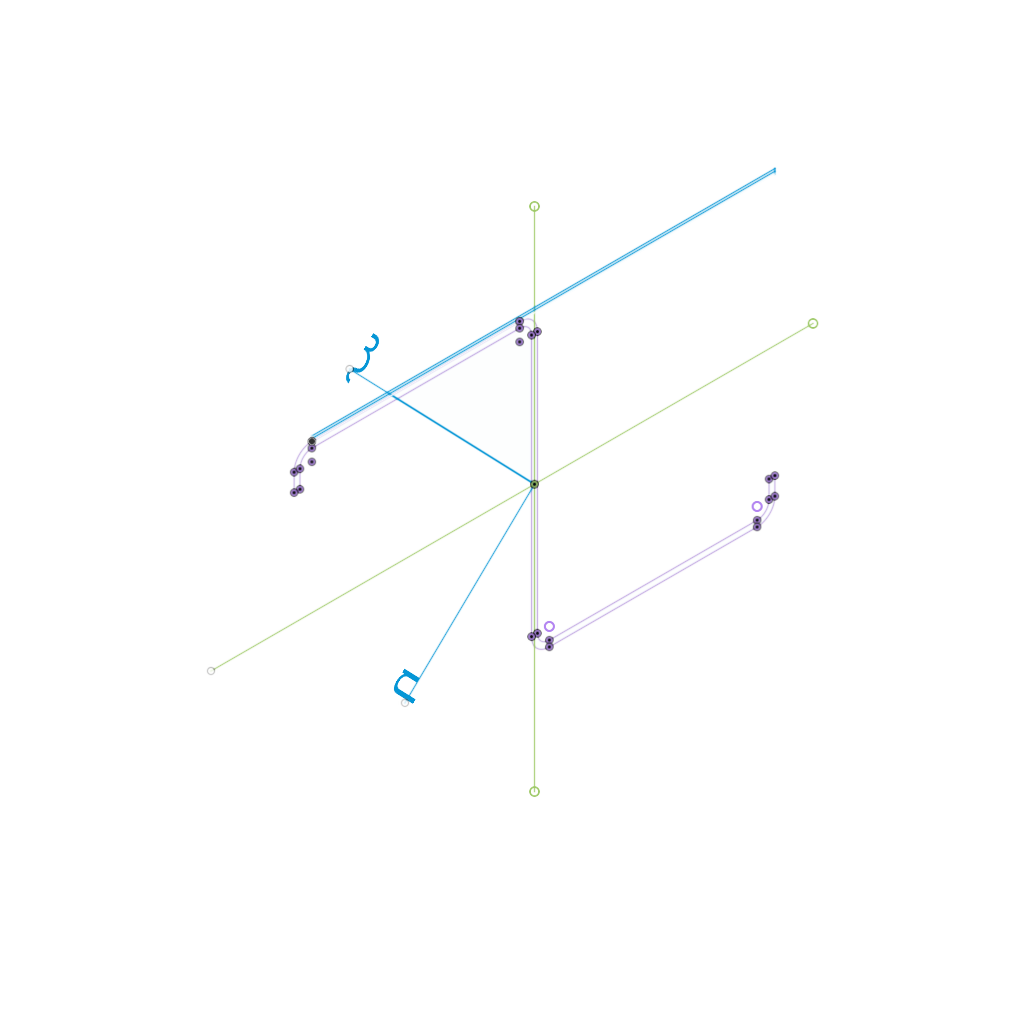
Modelo_3D (Autodesk Fusion 360 archive; units mm, degrees)
design "Configuration 1"
part number: 2026-10-21-11-30-17-065
Autodesk Fusion 360 part; units mm, degrees
sketch "Sketch1" plane through (0, 0, 0) normal (1, 0, 0) x (0, 0, -1)
  line L0 (49.5, 3, -90.5) -> (49.5, 47, -90.5)
  line L1 (50.5, 47, -90.5) -> (50.5, 3, -90.5)
  line L2 (52.5, 50, -90.5) -> (87.5, 50, -90.5)
  line L3 (87.5, 49, -90.5) -> (52.5, 49, -90.5)
  line L4 (12.5, 1, -90.5) -> (47.5, 1, -90.5)
  line L5 (9.5, 3, -90.5) -> (9.5, 6, -90.5)
  line L6 (9.5, 6, -90.5) -> (10.5, 6, -90.5)
  line L7 (10.5, 6, -90.5) -> (10.5, 3, -90.5)
  arc A0 through (10.5, 3, -90.5) (11.0858, 1.5858, -90.5) (12.5, 1, -90.5)
  arc A1 through (52.5, 49, -90.5) (51.0858, 48.4142, -90.5) (50.5, 47, -90.5)
  line L8 (12.5, 0, -90.5) -> (47.5, 0, -90.5)
  arc A2 through (47.5, 1, -90.5) (48.9142, 1.5858, -90.5) (49.5, 3, -90.5)
  line L9 (90.5, 47, -90.5) -> (90.5, 44, -90.5)
  line L10 (90.5, 44, -90.5) -> (89.5, 44, -90.5)
  line L11 (89.5, 44, -90.5) -> (89.5, 47, -90.5)
  arc A3 through (89.5, 47, -90.5) (88.9142, 48.4142, -90.5) (87.5, 49, -90.5)
  arc A4 through (52.5, 50, -90.5) (50.3787, 49.1213, -90.5) (49.5, 47, -90.5)
  arc A5 through (90.5, 47, -90.5) (89.6213, 49.1213, -90.5) (87.5, 50, -90.5)
  arc A6 through (9.5, 3, -90.5) (10.3787, 0.8787, -90.5) (12.5, 0, -90.5)
  arc A7 through (47.5, 0, -90.5) (49.6213, 0.8787, -90.5) (50.5, 3, -90.5)
  dimension "d21" = 3
  dimension "d22" = 3
  dimension "d24" = 3
extrude "Extrude1" add sketch "Sketch1" along normal blind 50 contours L0 L1 L2 L3 L4 L5 L6 L7 A0 A1 L8 A2 L9 L10 L11 A3 A4 A5 A6 A7 in plane through (-90.5, 0, 0) normal (1, 0, 0) makes body 1
ref_plane "WorkPlane2" through (-90.5, 25, -50) normal (1, 0, 0) x (0, 0, -1)
move_body "Move4" bodies 1 to x (1, 0, 0) y (0, 1, 0) z (0, 0, 1) at (90.5, 0, 9.5)
ref_plane "WorkPlane3" through (0, 25, -40.5) normal (-1, 0, 0) x (0, 0, 1)
sketch "Sketch6" plane through (0, 0, 0) normal (-1, 0, 0) x (0, 0, 1)
  arc A0 (-3, 0) -> (0, 3) centre (-3, 3) ccw
  line L0 (0, 3) -> (0, 6)
  line L1 (0, 6) -> (-1, 6)
  line L2 (-1, 6) -> (-1, 3)
  arc A1 (-3, 1) -> (-1, 3) centre (-3, 3) ccw
  line L3 (-3, 1) -> (-38, 1)
  arc A2 (-40, 3) -> (-38, 1) centre (-38, 3) ccw
  line L4 (-40, 3) -> (-40, 47)
  arc A3 (-40, 47) -> (-43, 50) centre (-43, 47) ccw
  line L5 (-43, 50) -> (-78, 50)
  arc A4 (-78, 50) -> (-81, 47) centre (-78, 47) ccw
  line L6 (-81, 47) -> (-81, 44)
  line L7 (-81, 44) -> (-80, 44)
  line L8 (-80, 44) -> (-80, 47)
  arc A5 (-78, 49) -> (-80, 47) centre (-78, 47) ccw
  line L9 (-78, 49) -> (-43, 49)
  arc A6 (-41, 47) -> (-43, 49) centre (-43, 47) ccw
  line L10 (-41, 47) -> (-41, 3)
  arc A7 (-41, 3) -> (-38, 0) centre (-38, 3) ccw
  line L11 (-38, 0) -> (-3, 0)
  line L12 (-81, 44) -> (-80, 44)
  line L13 (-80, 47) -> (-80, 44)
  line L14 (-81, 44) -> (-81, 47)
  line L15 (-78, 50) -> (-43, 50)
  line L16 (-43, 49) -> (-78, 49)
  line L17 (-41, 47) -> (-41, 3)
  line L18 (-38, 0) -> (-3, 0)
  line L19 (-38, 1) -> (-3, 1)
  line L20 (-1, 3) -> (-1, 6)
  line L21 (-1, 6) -> (0, 6)
  line L22 (0, 6) -> (0, 3)
  arc A8 (-3, 0) -> (0, 3) centre (-3, 3) ccw
  arc A9 (-3, 1) -> (-1, 3) centre (-3, 3) ccw
  arc A10 (-40, 5.2361) -> (-40.0006, 5.2355) centre (-38, 3) ccw
  arc A11 (-41, 3) -> (-38, 0) centre (-38, 3) ccw
  arc A12 (-40, 3) -> (-38, 1) centre (-38, 3) ccw
  arc A13 (-41, 47) -> (-43, 49) centre (-43, 47) ccw
  arc A14 (-78, 49) -> (-80, 47) centre (-78, 47) ccw
  arc A15 (-78, 50) -> (-81, 46.9985) centre (-78, 47) ccw
  line L23 (-40, 47) -> (-40, 3)
  arc A16 (-40, 47) -> (-43, 50) centre (-43, 47) ccw
  constraint coincident L6.end L7.start
  constraint coincident L7.end L8.start
  constraint coincident L8.end A5.end
  constraint coincident A4.end L6.start
  constraint coincident L5.end A4.start
  constraint coincident A3.end L5.start
  constraint coincident L9.end A6.end
  constraint coincident A5.start L9.start
  constraint coincident A6.start L10.start
  constraint coincident L10.end A7.start
  constraint coincident A7.end L11.start
  constraint coincident A0.start L11.end
  constraint coincident L3.end A2.end
  constraint coincident A1.start L3.start
  constraint coincident L2.end A1.end
  constraint coincident L1.end L2.start
  constraint coincident L0.end L1.start
  constraint coincident A0.end L0.start
  constraint concentric A0 A9
  constraint coincident L2.end A9
  constraint concentric A0 A8
  constraint concentric A2 A12
  constraint concentric A2 A11
  constraint coincident A7.end A11
  constraint coincident L4 A10.start
  constraint concentric A10 A11
  constraint concentric A6 A13
  constraint coincident L9.end A13
  constraint concentric A5 A15
  constraint coincident A4.end A15
  constraint concentric A4 A14
  constraint coincident A5.start A14
  constraint coincident L6 A15.end
  constraint coincident L4.end A3.start
  constraint coincident A2.start L4.start
  constraint concentric A3 A16
move_body "Move5" bodies 1 to x (1, 0, 0) y (0, 1, 0) z (0, 0, 1) at (0, 0, 80)
move_body "Move6" bodies 1 to x (1, 0, 0) y (0, 1, 0) z (0, 0, 1) at (0, -50, 0)
ref_plane "WorkPlane4" through (25, 0, 19.5) normal (0, 1, 0) x (0, 0, 1)
mirror "Mirror1" about plane through (25, 0, 19.5) normal (0, 1, 0) of bodies 1 makes body 2
move_body "Move7" bodies 2 to x (1, 0, 0) y (0, 1, 0) z (0, 0, 1) at (0, 0, 1)
sketch "Sketch8" plane through (0, 0, 0) normal (-1, 0, 0) x (0, 0, 1)
  arc A0 (81, 47) -> (78, 50) centre (78, 47) ccw
  line L0 (78, 50) -> (43, 50)
  arc A1 (43, 50) -> (40, 47) centre (43, 47) ccw
  line L1 (40, 47) -> (40, 3)
  arc A2 (38, 1) -> (40, 3) centre (38, 3) ccw
  line L2 (38, 1) -> (3, 1)
  arc A3 (1, 3) -> (3, 1) centre (3, 3) ccw
  line L3 (1, 3) -> (1, 6)
  line L4 (1, 6) -> (0, 6)
  line L5 (0, 6) -> (0, 3)
  arc A4 (0, 3) -> (3, 0) centre (3, 3) ccw
  line L6 (3, 0) -> (38, 0)
  arc A5 (38, 0) -> (41, 3) centre (38, 3) ccw
  line L7 (41, 3) -> (41, 47)
  arc A6 (43, 49) -> (41, 47) centre (43, 47) ccw
  line L8 (43, 49) -> (78, 49)
  arc A7 (80, 47) -> (78, 49) centre (78, 47) ccw
  line L9 (80, 47) -> (80, 44)
  line L10 (80, 44) -> (81, 44)
  line L11 (81, 44) -> (81, 47)
  line L12 (78, 50) -> (0, 50)
  line L13 (0, 50) -> (0, 50.8)
  line L14 (0, 50.8) -> (78, 50.8)
  line L15 (78, 50.8) -> (78, 50)
  line L16 (78, 50.4) -> (0, 50.4)
  line L17 (40.5, 24.9903) -> (71.6375, 57.3625)
  line L18 (40.5, 24.9903) -> (62.3226, 4)
  line L19 (40.5, 24.9903) -> (64.9406, 50.4)
  line L20 (40.5, 24.9903) -> (40.5, 65.5254)
  line L21 (40.5, 24.9903) -> (40.5, -19.8542)
  line L22 (40.5, 24.9903) -> (95, 24.9903)
  line L23 (40.5, 24.9903) -> (-6.4154, 24.9903)
  dimension "d45" = 35.2561
  dimension "d46" = 43.886
  dimension "d47" = 5
  dimension "d49" = 5
  constraint horizontal L12
  constraint vertical L13
  constraint horizontal L14
  constraint vertical L15
  constraint coincident A0.end L0.start
  constraint midpoint L15 L16.start
  constraint midpoint L13 L16.end
  constraint coincident L17.start L18.start
  constraint perpendicular L17 L18
  constraint perpendicular L18 L19
  constraint coincident L16 L19.end
  constraint parallel L1 L20
  constraint parallel L20 L21
  constraint perpendicular L21 L22
  constraint perpendicular L20 L23
  measures "d45" distance of L17.start L19.end
  measures "d46" angle of L17 L20
delete_body "RemoveBody1" bodies 1
hidden bodies 2
equation "d48 = 'ξ'"
equation "d50 = 'η'"

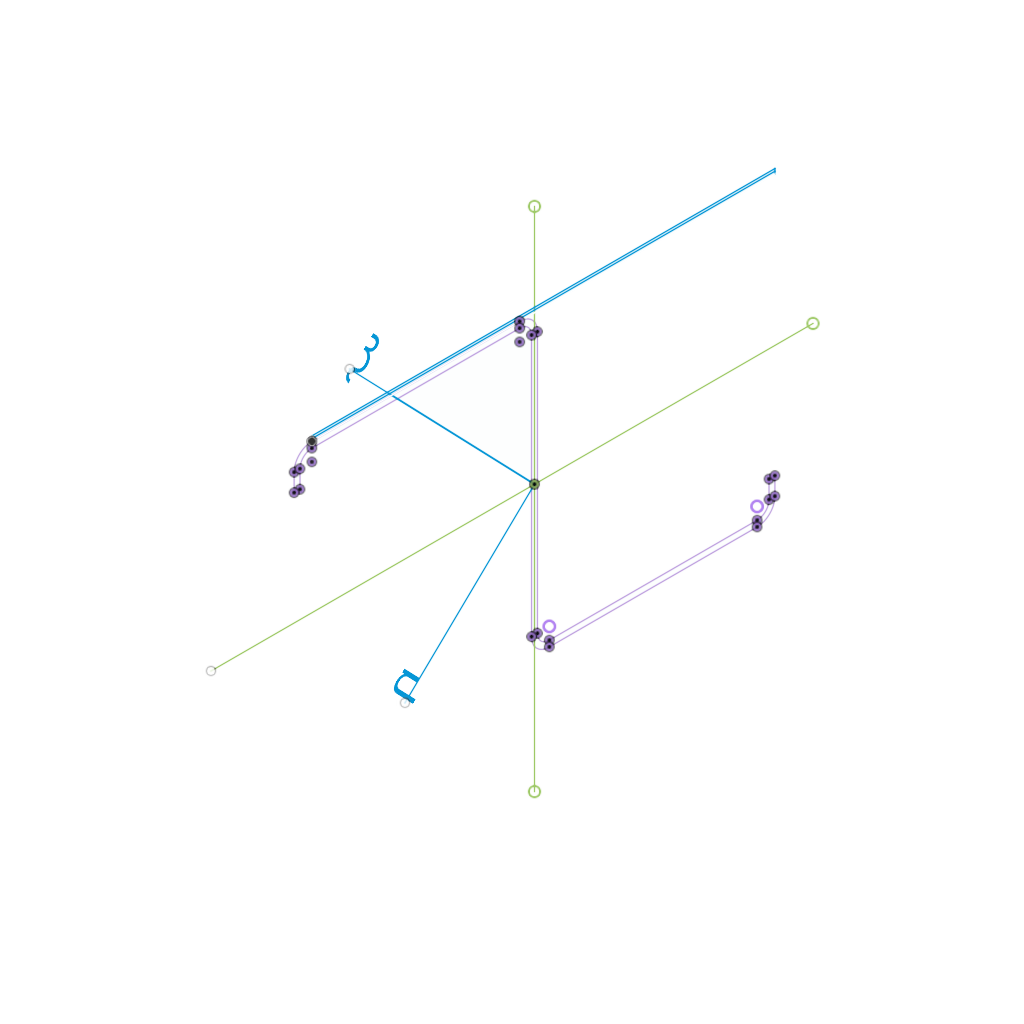
design "sketch viga z"
part number: 2026-10-21-11-30-17-065
Autodesk Fusion 360 part; units mm, degrees
sketch "Sketch1" plane through (0, 0, 0) normal (1, 0, 0) x (0, 0, -1)
  line L0 (49.5, 3, -90.5) -> (49.5, 47, -90.5)
  line L1 (50.5, 47, -90.5) -> (50.5, 3, -90.5)
  line L2 (52.5, 50, -90.5) -> (87.5, 50, -90.5)
  line L3 (87.5, 49, -90.5) -> (52.5, 49, -90.5)
  line L4 (12.5, 1, -90.5) -> (47.5, 1, -90.5)
  line L5 (9.5, 3, -90.5) -> (9.5, 6, -90.5)
  line L6 (9.5, 6, -90.5) -> (10.5, 6, -90.5)
  line L7 (10.5, 6, -90.5) -> (10.5, 3, -90.5)
  arc A0 through (10.5, 3, -90.5) (11.0858, 1.5858, -90.5) (12.5, 1, -90.5)
  arc A1 through (52.5, 49, -90.5) (51.0858, 48.4142, -90.5) (50.5, 47, -90.5)
  line L8 (12.5, 0, -90.5) -> (47.5, 0, -90.5)
  arc A2 through (47.5, 1, -90.5) (48.9142, 1.5858, -90.5) (49.5, 3, -90.5)
  line L9 (90.5, 47, -90.5) -> (90.5, 44, -90.5)
  line L10 (90.5, 44, -90.5) -> (89.5, 44, -90.5)
  line L11 (89.5, 44, -90.5) -> (89.5, 47, -90.5)
  arc A3 through (89.5, 47, -90.5) (88.9142, 48.4142, -90.5) (87.5, 49, -90.5)
  arc A4 through (52.5, 50, -90.5) (50.3787, 49.1213, -90.5) (49.5, 47, -90.5)
  arc A5 through (90.5, 47, -90.5) (89.6213, 49.1213, -90.5) (87.5, 50, -90.5)
  arc A6 through (9.5, 3, -90.5) (10.3787, 0.8787, -90.5) (12.5, 0, -90.5)
  arc A7 through (47.5, 0, -90.5) (49.6213, 0.8787, -90.5) (50.5, 3, -90.5)
  dimension "d21" = 3
  dimension "d22" = 3
  dimension "d24" = 3
extrude "Extrude1" add sketch "Sketch1" along normal blind 50 contours L0 L1 L2 L3 L4 L5 L6 L7 A0 A1 L8 A2 L9 L10 L11 A3 A4 A5 A6 A7 in plane through (-90.5, 0, 0) normal (1, 0, 0) makes body 1
ref_plane "WorkPlane2" through (-90.5, 25, -50) normal (1, 0, 0) x (0, 0, -1)
move_body "Move4" bodies 1 to x (1, 0, 0) y (0, 1, 0) z (0, 0, 1) at (90.5, 0, 9.5)
ref_plane "WorkPlane3" through (0, 25, -40.5) normal (-1, 0, 0) x (0, 0, 1)
sketch "Sketch6" plane through (0, 0, 0) normal (-1, 0, 0) x (0, 0, 1)
  arc A0 (-3, 0) -> (0, 3) centre (-3, 3) ccw
  line L0 (0, 3) -> (0, 6)
  line L1 (0, 6) -> (-1, 6)
  line L2 (-1, 6) -> (-1, 3)
  arc A1 (-3, 1) -> (-1, 3) centre (-3, 3) ccw
  line L3 (-3, 1) -> (-38, 1)
  arc A2 (-40, 3) -> (-38, 1) centre (-38, 3) ccw
  line L4 (-40, 3) -> (-40, 47)
  arc A3 (-40, 47) -> (-43, 50) centre (-43, 47) ccw
  line L5 (-43, 50) -> (-78, 50)
  arc A4 (-78, 50) -> (-81, 47) centre (-78, 47) ccw
  line L6 (-81, 47) -> (-81, 44)
  line L7 (-81, 44) -> (-80, 44)
  line L8 (-80, 44) -> (-80, 47)
  arc A5 (-78, 49) -> (-80, 47) centre (-78, 47) ccw
  line L9 (-78, 49) -> (-43, 49)
  arc A6 (-41, 47) -> (-43, 49) centre (-43, 47) ccw
  line L10 (-41, 47) -> (-41, 3)
  arc A7 (-41, 3) -> (-38, 0) centre (-38, 3) ccw
  line L11 (-38, 0) -> (-3, 0)
  line L12 (-81, 44) -> (-80, 44)
  line L13 (-80, 47) -> (-80, 44)
  line L14 (-81, 44) -> (-81, 47)
  line L15 (-78, 50) -> (-43, 50)
  line L16 (-43, 49) -> (-78, 49)
  line L17 (-41, 47) -> (-41, 3)
  line L18 (-38, 0) -> (-3, 0)
  line L19 (-38, 1) -> (-3, 1)
  line L20 (-1, 3) -> (-1, 6)
  line L21 (-1, 6) -> (0, 6)
  line L22 (0, 6) -> (0, 3)
  arc A8 (-3, 0) -> (0, 3) centre (-3, 3) ccw
  arc A9 (-3, 1) -> (-1, 3) centre (-3, 3) ccw
  arc A10 (-40, 5.2361) -> (-40.0006, 5.2355) centre (-38, 3) ccw
  arc A11 (-41, 3) -> (-38, 0) centre (-38, 3) ccw
  arc A12 (-40, 3) -> (-38, 1) centre (-38, 3) ccw
  arc A13 (-41, 47) -> (-43, 49) centre (-43, 47) ccw
  arc A14 (-78, 49) -> (-80, 47) centre (-78, 47) ccw
  arc A15 (-78, 50) -> (-81, 46.9985) centre (-78, 47) ccw
  line L23 (-40, 47) -> (-40, 3)
  arc A16 (-40, 47) -> (-43, 50) centre (-43, 47) ccw
  constraint coincident L6.end L7.start
  constraint coincident L7.end L8.start
  constraint coincident L8.end A5.end
  constraint coincident A4.end L6.start
  constraint coincident L5.end A4.start
  constraint coincident A3.end L5.start
  constraint coincident L9.end A6.end
  constraint coincident A5.start L9.start
  constraint coincident A6.start L10.start
  constraint coincident L10.end A7.start
  constraint coincident A7.end L11.start
  constraint coincident A0.start L11.end
  constraint coincident L3.end A2.end
  constraint coincident A1.start L3.start
  constraint coincident L2.end A1.end
  constraint coincident L1.end L2.start
  constraint coincident L0.end L1.start
  constraint coincident A0.end L0.start
  constraint concentric A0 A9
  constraint coincident L2.end A9
  constraint concentric A0 A8
  constraint concentric A2 A12
  constraint concentric A2 A11
  constraint coincident A7.end A11
  constraint coincident L4 A10.start
  constraint concentric A10 A11
  constraint concentric A6 A13
  constraint coincident L9.end A13
  constraint concentric A5 A15
  constraint coincident A4.end A15
  constraint concentric A4 A14
  constraint coincident A5.start A14
  constraint coincident L6 A15.end
  constraint coincident L4.end A3.start
  constraint coincident A2.start L4.start
  constraint concentric A3 A16
move_body "Move5" bodies 1 to x (1, 0, 0) y (0, 1, 0) z (0, 0, 1) at (0, 0, 80)
move_body "Move6" bodies 1 to x (1, 0, 0) y (0, 1, 0) z (0, 0, 1) at (0, -50, 0)
ref_plane "WorkPlane4" through (25, 0, 19.5) normal (0, 1, 0) x (0, 0, 1)
mirror "Mirror1" about plane through (25, 0, 19.5) normal (0, 1, 0) of bodies 1 makes body 2
move_body "Move7" bodies 2 to x (1, 0, 0) y (0, 1, 0) z (0, 0, 1) at (0, 0, 1)
sketch "Sketch8" plane through (0, 0, 0) normal (-1, 0, 0) x (0, 0, 1)
  arc A0 (81, 47) -> (78, 50) centre (78, 47) ccw
  line L0 (78, 50) -> (43, 50)
  arc A1 (43, 50) -> (40, 47) centre (43, 47) ccw
  line L1 (40, 47) -> (40, 3)
  arc A2 (38, 1) -> (40, 3) centre (38, 3) ccw
  line L2 (38, 1) -> (3, 1)
  arc A3 (1, 3) -> (3, 1) centre (3, 3) ccw
  line L3 (1, 3) -> (1, 6)
  line L4 (1, 6) -> (0, 6)
  line L5 (0, 6) -> (0, 3)
  arc A4 (0, 3) -> (3, 0) centre (3, 3) ccw
  line L6 (3, 0) -> (38, 0)
  arc A5 (38, 0) -> (41, 3) centre (38, 3) ccw
  line L7 (41, 3) -> (41, 47)
  arc A6 (43, 49) -> (41, 47) centre (43, 47) ccw
  line L8 (43, 49) -> (78, 49)
  arc A7 (80, 47) -> (78, 49) centre (78, 47) ccw
  line L9 (80, 47) -> (80, 44)
  line L10 (80, 44) -> (81, 44)
  line L11 (81, 44) -> (81, 47)
  line L12 (78, 50) -> (0, 50)
  line L13 (0, 50) -> (0, 50.8)
  line L14 (0, 50.8) -> (78, 50.8)
  line L15 (78, 50.8) -> (78, 50)
  line L16 (78, 50.4) -> (0, 50.4)
  line L17 (40.5, 24.9903) -> (71.6375, 57.3625)
  line L18 (40.5, 24.9903) -> (62.3226, 4)
  line L19 (40.5, 24.9903) -> (64.9406, 50.4)
  line L20 (40.5, 24.9903) -> (40.5, 65.5254)
  line L21 (40.5, 24.9903) -> (40.5, -19.8542)
  line L22 (40.5, 24.9903) -> (95, 24.9903)
  line L23 (40.5, 24.9903) -> (-6.4154, 24.9903)
  dimension "d45" = 35.2561
  dimension "d46" = 43.886
  dimension "d47" = 5
  dimension "d49" = 5
  constraint horizontal L12
  constraint vertical L13
  constraint horizontal L14
  constraint vertical L15
  constraint coincident A0.end L0.start
  constraint midpoint L15 L16.start
  constraint midpoint L13 L16.end
  constraint coincident L17.start L18.start
  constraint perpendicular L17 L18
  constraint perpendicular L18 L19
  constraint coincident L16 L19.end
  constraint parallel L1 L20
  constraint parallel L20 L21
  constraint perpendicular L21 L22
  constraint perpendicular L20 L23
  measures "d45" distance of L17.start L19.end
  measures "d46" angle of L17 L20
delete_body "RemoveBody1" bodies 1
hidden bodies 2
equation "d48 = 'ξ'"
equation "d50 = 'η'"

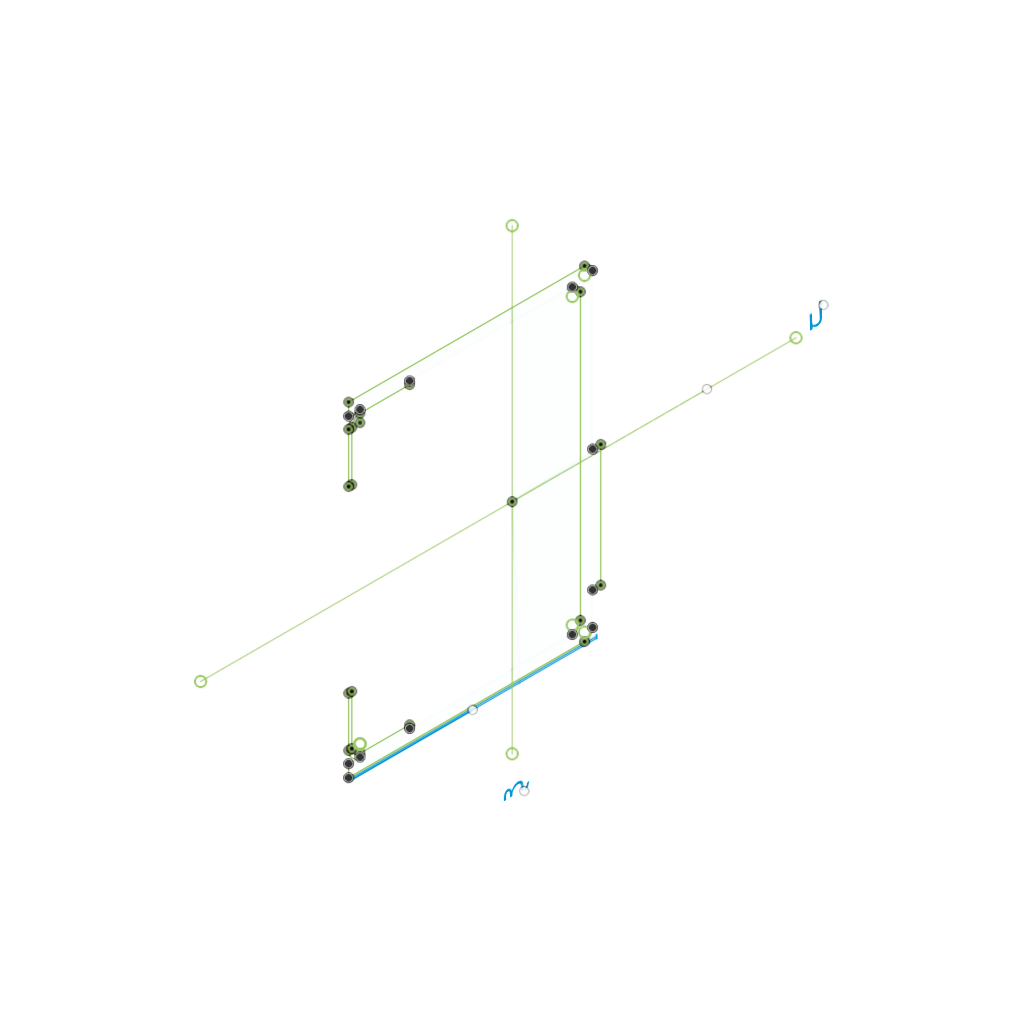
design "sketch viga c"
part number: 2026-10-21-11-20-21-009
Autodesk Fusion 360 part; units mm, degrees
derive "DerivedContext1"
sketch "Sketch1" plane through (0, 0, 0) normal (1, 0, 0) x (0, 0, -1)
  line L0 (0, 0) -> (-60, 0)
  line L1 (-60, 80) -> (0, 80)
  line L2 (0, 80) -> (0, 0)
  line L3 (-57, 77) -> (-3, 77)
  line L4 (-3, 77) -> (-3, 3)
  line L5 (-3, 3) -> (-57, 3)
  line L6 (-57, 77) -> (-60, 77)
  line L7 (-57, 3) -> (-60, 3)
  line L8 (-60, 0) -> (-60, 3)
  line L9 (-60, 77) -> (-60, 80)
  line L10 (0, 80) -> (0, 70)
  line L11 (0, 70) -> (2, 70)
  line L12 (2, 70) -> (2, 40)
  line L13 (2, 40) -> (0, 40)
  line L14 (-57.2, 77) -> (-45, 77)
  line L15 (-60, 74.2) -> (-60, 62)
  line L16 (-60, 62) -> (-59.2, 62)
  line L17 (-45, 77) -> (-45, 76.2)
  line L18 (-45, 76.2) -> (-57.2, 76.2)
  line L19 (-59.2, 62) -> (-59.2, 74.2)
  line L20 (-59.2, 77) -> (-59.2, 77.0004)
  arc A0 (-57.2, 76.2) -> (-59.2, 74.2) centre (-57.2, 74.2) ccw
  line L21 (-57.2, 3) -> (-45, 3)
  line L22 (-60, 5.8) -> (-60, 18)
  line L23 (-60, 18) -> (-59.2, 18)
  line L24 (-45, 3) -> (-45, 3.8)
  line L25 (-45, 3.8) -> (-57.2, 3.8)
  line L26 (-59.2, 5.8) -> (-59.2, 18)
  arc A1 (-59.2, 5.8) -> (-57.2, 3.8) centre (-57.2, 5.8) ccw
  arc A2 (-57.2, 77) -> (-60, 74.2) centre (-57.2, 74.2) ccw
  arc A3 (-60, 5.8) -> (-57.2, 3) centre (-57.2, 5.8) ccw
  point P0 (-30, 40)
  dimension "d9" = 15
  dimension "d32" = 2.8
  dimension "d33" = 2.8
  constraint horizontal L0
  constraint vertical L8
  constraint horizontal L1
  constraint vertical L2
  constraint coincident L0.start L2.end
  constraint horizontal L3
  constraint perpendicular L3 L4
  constraint parallel L3 L5
  constraint perpendicular L6 L9
  constraint perpendicular L7 L8
  constraint collinear L8 L9
  constraint perpendicular L1 L10
  constraint perpendicular L2 L11
  constraint perpendicular L11 L12
  constraint perpendicular L2 L13
  constraint perpendicular L9 L14
  constraint perpendicular L14 L15
  constraint perpendicular L15 L16
  constraint vertical L19
  constraint perpendicular L14 L17
  constraint perpendicular L18 L19
  constraint coincident L6 L20.start
  constraint collinear L19 L20
  constraint tangent L18 A0
  constraint tangent L19 A0
  constraint coincident L6.end L14
  constraint coincident L6.end L15
  constraint perpendicular L8 L21
  constraint perpendicular L21 L22
  constraint perpendicular L22 L23
  constraint perpendicular L21 L24
  constraint perpendicular L22 L25
  constraint perpendicular L23 L26
  constraint tangent L25 A1
  constraint tangent L26 A1
  constraint coincident L7.end L21
  constraint coincident L7.end L22
  constraint tangent L14 A2
  constraint tangent L15 A2
  constraint tangent L22 A3
  constraint tangent L21 A3
  measures "d9" distance of L6.end L14.end
  measures "d32" radius of A2
  measures "d33" radius of A3
extrude "Extrude1" add sketch "Sketch1" along normal blind 50 contours L0 L1 L2 L3 L4 L5 L6 L7 L8 L9 L10 L14 L21 makes body 1
extrude "Extrude2" add sketch "Sketch1" along normal blind 50 separate body contours L3 L6 L14 L15 L16 L17 L18 L19 A0 A2 makes body 2
extrude "Extrude3" add sketch "Sketch1" along normal blind 50 separate body contours L5 L7 L21 L22 L23 L24 L25 L26 A1 A3 makes body 3
extrude "Extrude4" add sketch "Sketch1" along normal blind 50 separate body contours L2 L11 L12 L13 makes body 4
fillet "Fillet1" radius 2 4 edges at (25, 0, 0) (25, 80, 0) (25, 77, 3) (25, 3, 3) on bodies 1
move_body "Move1" bodies 2 3 4 1 to x (1, 0, 0) y (0, 1, 0) z (0, 0, 1) at (0, 0, -60)
sketch "Sketch3" plane through (50, 0, 0) normal (1, 0, 0) x (0, 0, -1)
  arc A0 (60, 78) -> (58, 80) centre (58, 78) ccw
  line L0 (58, 80) -> (0, 80)
  line L1 (0, 80) -> (0, 77)
  line L2 (0, 77) -> (55, 77)
  arc A1 (57, 75) -> (55, 77) centre (55, 75) ccw
  line L3 (57, 75) -> (57, 5)
  arc A2 (55, 3) -> (57, 5) centre (55, 5) ccw
  line L4 (55, 3) -> (0, 3)
  line L5 (0, 3) -> (0, 0)
  line L6 (0, 0) -> (58, 0)
  arc A3 (58, 0) -> (60, 2) centre (58, 2) ccw
  line L7 (60, 2) -> (60, 78)
  line L8 (60, 70) -> (60, 40)
  line L9 (60, 40) -> (62, 40)
  line L10 (62, 40) -> (62, 70)
  line L11 (62, 70) -> (60, 70)
  arc A4 (2.8, 77) -> (0, 74.2) centre (2.8, 74.2) ccw
  line L12 (0, 74.2) -> (0, 62)
  line L13 (0, 62) -> (0.8, 62)
  line L14 (0.8, 62) -> (0.8, 74.2)
  arc A5 (2.8, 76.2) -> (0.8, 74.2) centre (2.8, 74.2) ccw
  line L15 (2.8, 76.2) -> (15, 76.2)
  line L16 (15, 76.2) -> (15, 77)
  line L17 (15, 77) -> (2.8, 77)
  line L18 (15, 3) -> (15, 3.8)
  line L19 (15, 3.8) -> (2.8, 3.8)
  arc A6 (0.8, 5.8) -> (2.8, 3.8) centre (2.8, 5.8) ccw
  line L20 (0.8, 5.8) -> (0.8, 18)
  line L21 (0.8, 18) -> (0, 18)
  line L22 (0, 18) -> (0, 5.8)
  arc A7 (0, 5.8) -> (2.8, 3) centre (2.8, 5.8) ccw
  line L23 (2.8, 3) -> (15, 3)
sketch "Sketch4" plane through (0, 0, 0) normal (-1, 0, 0) x (0, 0, -1)
  arc A0 (60, 78) -> (58, 80) centre (58, 78) ccw
  line L0 (58, 80) -> (0, 80)
  line L1 (0, 80) -> (0, 77)
  arc A1 (57, 75) -> (55, 77) centre (55, 75) ccw
  line L2 (57, 75) -> (57, 5)
  arc A2 (55, 3) -> (57, 5) centre (55, 5) ccw
  line L3 (0, 3) -> (0, 0)
  line L4 (0, 0) -> (58, 0)
  arc A3 (58, 0) -> (60, 2) centre (58, 2) ccw
  line L5 (60, 40) -> (62, 40)
  line L6 (62, 40) -> (62, 70)
  line L7 (62, 70) -> (60, 70)
  arc A4 (2.8, 77) -> (0, 74.2) centre (2.8, 74.2) ccw
  line L8 (0, 74.2) -> (0, 62)
  line L9 (0, 62) -> (0.8, 62)
  line L10 (0.8, 62) -> (0.8, 74.2)
  arc A5 (2.8, 76.2) -> (0.8, 74.2) centre (2.8, 74.2) ccw
  line L11 (2.8, 76.2) -> (15, 76.2)
  line L12 (15, 76.2) -> (15, 77)
  line L13 (15, 3) -> (15, 3.8)
  line L14 (15, 3.8) -> (2.8, 3.8)
  arc A6 (0.8, 5.8) -> (2.8, 3.8) centre (2.8, 5.8) ccw
  line L15 (0.8, 5.8) -> (0.8, 18)
  line L16 (0.8, 18) -> (0, 18)
  line L17 (0, 18) -> (0, 5.8)
  arc A7 (0, 5.8) -> (2.8, 3) centre (2.8, 5.8) ccw
  line L18 (0, 3) -> (2.8, 3)
  line L19 (55, 3) -> (15, 3)
  line L20 (0, 77) -> (2.8, 77)
  line L21 (15, 77) -> (55, 77)
  line L22 (60, 78) -> (60, 70)
  line L23 (60, 40) -> (60, 2)
  line L24 (0, 80) -> (61, 80)
  line L25 (61, 80) -> (61, 80.8)
  line L26 (61, 80.8) -> (0, 80.8)
  line L27 (0, 80.8) -> (0, 80)
  line L28 (61, 80.4) -> (0, 80.4)
  line L29 (40.21, 41.31) -> (-36.3838, 41.31)
  line L30 (40.21, 41.31) -> (40.21, -17.4464)
  line L31 (40.21, 41.31) -> (110, 41.31)
  line L32 (40.21, 41.31) -> (40.21, 95)
  line L33 (40.21, 41.31) -> (116.7231, 37.7029)
  line L34 (40.21, 41.31) -> (88.095, 41.31) construction
  line L35 (40.21, 41.31) -> (43.1857, 104.4303)
  line L36 (0, 80.8) -> (30.5, 80.8)
  dimension "d41" = 2.699
  dimension "d42" = 5
  dimension "d44" = 5
  dimension "d46" = 30.5
  constraint coincident L3.start L18.start
  constraint coincident A7.end L18.end
  constraint coincident A2.start L19.start
  constraint coincident L13.start L19.end
  constraint coincident L1.end L20.start
  constraint coincident A4.start L20.end
  constraint coincident L12.end L21.start
  constraint coincident A1.end L21.end
  constraint coincident A0.start L22.start
  constraint coincident L7.end L22.end
  constraint coincident L5.start L23.start
  constraint coincident A3.end L23.end
  constraint horizontal L24
  constraint vertical L25
  constraint horizontal L26
  constraint vertical L27
  constraint coincident L0.end L1.start
  constraint midpoint L25 L28.start
  constraint midpoint L27 L28.end
  constraint perpendicular L29 L30
  constraint perpendicular L2 L31
  constraint perpendicular L21 L32
  constraint horizontal L34
  constraint coincident L29.start L30.start
  constraint perpendicular L33 L35
  constraint perpendicular L27 L36
  measures "d41" angle of L33 L34
  measures "d46" distance of L26.end L36.end
hidden bodies 1 2 3 4
equation "d43 = ' ξ'"
equation "d45 = 'η'"
equation "d46 = ( 61 / 2 ) * 1 mm"
